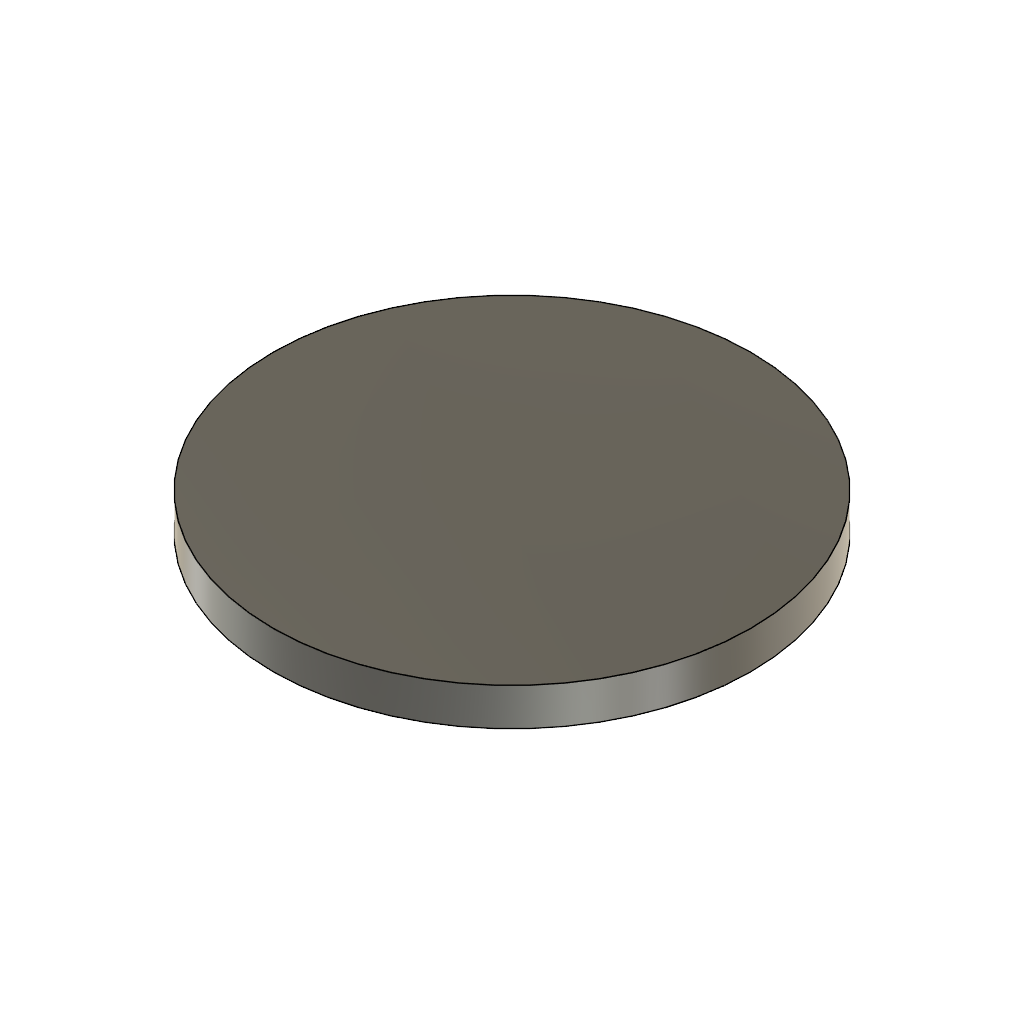
Rückwand (Autodesk Fusion 360 design; units mm, degrees)
part number: 2026-10-08-12-39-34-155
Autodesk Fusion 360 part; units mm, degrees
sketch "Skizze1" plane through (0, 0, 0) normal (0, 0, 1) x (1, 0, 0)
  circle A0 centre (0, 0) radius 63.5
  dimension "d3" = 127
  constraint coincident A0.centre origin
  measures "d3" diameter of A0
extrude "Extrusion1" add sketch "Skizze1" along normal blind 10
